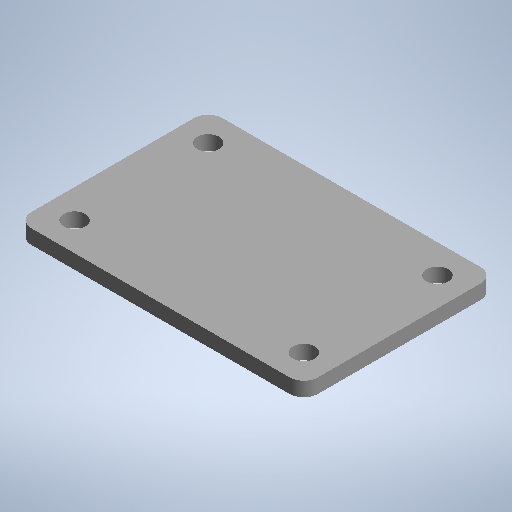
# Autodesk Inventor part: MountingPlate
Saved by Autodesk Inventor 2027 (Build 310192060, 192F)
## iProperties
Part Number: MountingPlate
Material: Generic
Description: Mounting plate 120 x 80 x 6 mm
Document SubType Name: Modeling
Designer: tobias
Stock Number: PL6-120x80
Appearance: Default
RuleStatus: InUse
BeforeDocSave0: UpdateDescription
BeforeDocSave1: CheckHoleEdgeDistance
AfterAnyUserParamChange0: CheckHoleEdgeDistance
Title: Mounting plate
Author: tobias
Autodesk Inventor part; units mm, degrees
ref_plane "YZ Plane" through (0, 0, 0) normal (1, 0, 0) x (0, 1, 0)
ref_plane "XZ Plane" through (0, 0, 0) normal (0, 1, 0) x (-1, 0, 0)
ref_plane "XY Plane" through (0, 0, 0) normal (0, 0, 1) x (1, 0, 0)
sketch "Sketch1" plane through (0, 0, 0) normal (0, 1, 0) x (-1, 0, 0)
  line L0 (-600, -400) -> (600, -400)
  line L1 (600, -400) -> (600, 400)
  line L2 (600, 400) -> (-600, 400)
  line L3 (-600, 400) -> (-600, -400)
  circle A0 centre (-480, -280) radius 45
  circle A1 centre (480, -280) radius 45
  circle A2 centre (480, 280) radius 45
  circle A3 centre (-480, 280) radius 45
  point P0 (0, 0)
  dimension "d0" = 1200
  dimension "d1" = 800
  dimension "d2" = 600
  dimension "d3" = 400
  dimension "d4" = 480
  dimension "d5" = 280
  dimension "d6" = 90
  dimension "d7" = 480
  dimension "d8" = 280
  dimension "d9" = 480
  dimension "d10" = 280
  dimension "d11" = 480
  dimension "d12" = 280
  constraints: 8 end point, 4 centre point, 3 equal radius, 2 parallel, 1 horizontal, 1 perpendicular
  measures "d0" distance of L0.start L0.end
  measures "d1" distance of L0.end L1.end
  measures "d2" horizontal distance of point (0, 0) L0.start
  measures "d3" vertical distance of point (0, 0) L0.start
  measures "d4" horizontal distance of point (0, 0) A0.centre
  measures "d5" vertical distance of point (0, 0) A0.centre
  measures "d6" diameter of A0
  measures "d7" horizontal distance of point (0, 0) A1.centre
  measures "d8" vertical distance of point (0, 0) A1.centre
  measures "d9" horizontal distance of point (0, 0) A2.centre
  measures "d10" vertical distance of point (0, 0) A2.centre
  measures "d11" horizontal distance of point (0, 0) A3.centre
  measures "d12" vertical distance of point (0, 0) A3.centre
extrude "Extrusion1" add sketch "Sketch1" along normal blind 60
fillet "Fillet1" radius 60 4 edges at (600, 30, -400) (600, 30, 400) (-600, 30, 400) (-600, 30, -400)
equation "\"d0\" = Length"
equation "\"d1\" = Width"
equation "\"d2\" = 0.5 * Length"
equation "\"d3\" = 0.5 * Width"
equation "\"d4\" = 0.5 * Length - Inset"
equation "\"d5\" = 0.5 * Width - Inset"
equation "\"d6\" = HoleDia"
equation "\"d7\" = 0.5 * Length - Inset"
equation "\"d8\" = 0.5 * Width - Inset"
equation "\"d9\" = 0.5 * Length - Inset"
equation "\"d10\" = 0.5 * Width - Inset"
equation "\"d11\" = 0.5 * Length - Inset"
equation "\"d12\" = 0.5 * Width - Inset"
equation "\"d13\" = Thickness"
equation "\"d15\" = 0.5 * Inset"
equation "\"Length\" = 1200"
equation "\"Width\" = 800"
equation "\"Thickness\" = 60"
equation "\"HoleDia\" = 90"
equation "\"Inset\" = 120"
body "Solid1"
